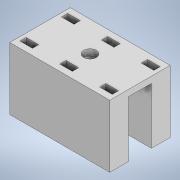
# Autodesk Inventor part: ghidaj_gaura
Saved by Autodesk Inventor 2022.6 (Build 266554000, 554)
## iProperties
Created: 2026-01-10
Part Number: ghidaj_gaura
Material: Generic
Document SubType Name: Modeling
Designer: Dragos Macovei
Density: 1 g/cm^3
Appearance: Default
Author: Dragos Macovei
Autodesk Inventor part; units mm, degrees
ref_plane "YZ Plane" through (0, 0, 0) normal (1, 0, 0) x (0, 1, 0)
ref_plane "XZ Plane" through (0, 0, 0) normal (0, 1, 0) x (-1, 0, 0)
ref_plane "XY Plane" through (0, 0, 0) normal (0, 0, 1) x (1, 0, 0)
sketch "Sketch1" plane through (0, 0, 0) normal (0, 1, 0) x (-1, 0, 0)
  line L0 (0, 0) -> (80, 0)
  line L1 (80, 0) -> (80, 18.3)
  line L2 (80, 18.3) -> (0, 18.3)
  line L3 (0, 18.3) -> (0, 0)
  dimension "d0" = 80
  dimension "d1" = 18.3
  constraints: 8 end point, 2 parallel, 1 horizontal, 1 perpendicular
  measures "d0" distance of L2.end L1.end
  measures "d1" distance of L0.end L1.end
extrude "Extrusion1" add sketch "Sketch1" along normal blind 5
sketch "Sketch2" plane through (0, 5, 0) normal (0, 1, 0) x (1, 0, 0)
  line L0 (-80, 0) -> (-80, -18.3) projected
  line L1 (-80, -18.3) -> (0, -18.3) projected
  line L2 (0, -18.3) -> (0, 0) projected
  line L3 (0, 0) -> (-80, 0) projected
  circle A0 centre (-40, -9.15) radius 5.05
  circle A1 centre (-40, -9.15) radius 9.15
  line L4 (0, 0) -> (-80, 0) projected
  dimension "d4" = 10.1
  constraints: 2 centre point, 1 coincident, 1 tangent
  measures "d4" diameter of A0
extrude "Extrusion2" cut sketch "Sketch2" against normal blind 5 contours A0
sketch "Sketch3" plane through (0, 5, 0) normal (0, 1, 0) x (1, 0, 0)
  circle A0 centre (-40, -9.15) radius 5.05 projected
  line L0 (-80, 0) -> (-80, -18.3) projected
  line L1 (-80, -18.3) -> (0, -18.3) projected
  line L2 (0, -18.3) -> (0, 0) projected
  line L3 (0, 0) -> (-80, 0) projected
  line L4 (-80, -18.3) -> (0, -18.3) projected
  line L5 (-80, -18.3) -> (0, -18.3)
  line L6 (0, -18.3) -> (0, -28.3)
  line L7 (0, -28.3) -> (-80, -28.3)
  line L8 (-80, -28.3) -> (-80, -18.3)
  line L9 (0, 0) -> (-80, 0) projected
  line L10 (-80, 0) -> (0, 0)
  line L11 (0, 0) -> (0, 10)
  line L12 (0, 10) -> (-80, 10)
  line L13 (-80, 10) -> (-80, 0)
  dimension "d7" = 10
  dimension "d8" = 10
  constraints: 16 end point, 4 parallel, 2 horizontal, 2 perpendicular, 1 point on line
  measures "d7" distance of L5.end L6.end
  measures "d8" distance of L11.end L10.end
extrude "Extrusion3" add sketch "Sketch3" against normal blind 50 contours L13 L12 L11 L3 | L1 L6 L7 L8
sketch "Sketch4" plane through (0, 5, 0) normal (0, 1, 0) x (1, 0, 0)
  circle A0 centre (-40, -9.15) radius 5.05 projected
  line L0 (-80, 10) -> (-80, -28.3) projected
  line L1 (-80, -28.3) -> (0, -28.3) projected
  line L2 (0, -28.3) -> (0, 10) projected
  line L3 (0, 10) -> (-80, 10) projected
  line L4 (0, -28.3) -> (-80, -28.3) projected
  line L5 (-80, 10) -> (0, 10) projected
  line L6 (-45.05, -28.3) -> (-34.95, -28.3)
  line L7 (-34.95, -28.3) -> (-34.95, -23.3)
  line L8 (-34.95, -23.3) -> (-45.05, -23.3)
  line L9 (-45.05, -23.3) -> (-45.05, -28.3)
  line L10 (-45.05, 10) -> (-34.95, 10)
  line L11 (-34.95, 10) -> (-34.95, 5)
  line L12 (-34.95, 5) -> (-45.05, 5)
  line L13 (-45.05, 5) -> (-45.05, 10)
  point P0 (0, 0)
  point P1 (-40, -28.3)
  point P2 (-40, 10)
  dimension "d11" = 5
  dimension "d12" = 5
  constraints: 16 end point, 5 point on line, 4 parallel, 2 horizontal, 2 midpoint, 2 perpendicular
  measures "d11" distance of L7.end L6.end
  measures "d12" distance of L10.end L11.end
extrude "Extrusion4" cut sketch "Sketch4" against normal through all contours L3 L11 L12 L13 | L9 L8 L7 L1
sketch "Sketch5" plane through (0, 5, 0) normal (0, 1, 0) x (1, 0, 0)
  line L0 (-34.95, 10) -> (-34.95, 5) projected
  line L1 (-34.95, 5) -> (-45.05, 5) projected
  line L2 (-45.05, 5) -> (-45.05, 10) projected
  line L3 (-45.05, 10) -> (-80, 10) projected
  line L4 (-80, 10) -> (-80, -28.3) projected
  line L5 (-80, -28.3) -> (-45.05, -28.3) projected
  line L6 (-45.05, -28.3) -> (-45.05, -23.3) projected
  line L7 (-45.05, -23.3) -> (-34.95, -23.3) projected
  line L8 (-34.95, -23.3) -> (-34.95, -28.3) projected
  line L9 (-34.95, -28.3) -> (0, -28.3) projected
  line L10 (0, -28.3) -> (0, 10) projected
  line L11 (0, 10) -> (-34.95, 10) projected
  circle A0 centre (-40, -9.15) radius 5.05 projected
  line L12 (-45.05, -28.3) -> (-80, -28.3) projected
  line L13 (-80, 10) -> (-45.05, 10) projected
  line L14 (-77, -28.3) -> (-66.9, -28.3)
  line L15 (-66.9, -28.3) -> (-66.9, -23.3)
  line L16 (-66.9, -23.3) -> (-77, -23.3)
  line L17 (-77, -23.3) -> (-77, -28.3)
  line L18 (-77, 10) -> (-66.9, 10)
  line L19 (-66.9, 10) -> (-66.9, 5)
  line L20 (-66.9, 5) -> (-77, 5)
  line L21 (-77, 5) -> (-77, 10)
  line L22 (0, 10) -> (0, 0) projected
  line L23 (-34.95, -28.3) -> (0, -28.3) projected
  line L24 (-13.1, -28.3) -> (-3, -28.3)
  line L25 (-3, -28.3) -> (-3, -23.3)
  line L26 (-3, -23.3) -> (-13.1, -23.3)
  line L27 (-13.1, -23.3) -> (-13.1, -28.3)
  line L28 (-13.1, 10) -> (-3, 10)
  line L29 (-3, 10) -> (-3, 5)
  line L30 (-3, 5) -> (-13.1, 5)
  line L31 (-13.1, 5) -> (-13.1, 10)
  point P0 (-66.9, 10)
  point P1 (-77, -25.8)
  point P2 (-77, 7.5)
  point P3 (-3, -25.8)
  point P4 (-8.05, -28.3)
  point P5 (-8.05, -23.3)
  point P6 (-8.05, 10)
  point P7 (-8.05, 5)
  point P8 (-3, 7.5)
  point P9 (-3, 10)
  point P10 (-3, -28.3)
  dimension "d15" = 10.1
  dimension "d16" = 10.1
  dimension "d21" = 3
  dimension "d22" = 10.1
  dimension "d23" = 3
  dimension "d24" = 3
  dimension "d25" = 10.1
  dimension "d26" = 5
  dimension "d27" = 5
  dimension "d28" = 5
  dimension "d29" = 10.1
  dimension "d30" = 3
  constraints: 32 end point, 8 midpoint, 8 parallel, 7 point on line, 4 horizontal, 4 perpendicular
  measures "d15" distance of point (-66.9, -28.3) L14.start
  measures "d16" distance of point (-66.9, 10) L18.start
  measures "d21" distance from line of point (-77, -25.8) L4
  measures "d22" distance between parallel lines of L15 L17
  measures "d23" distance from line of point (-77, 7.5) L4
  measures "d24" distance from line of L10 point (-3, -25.8)
  measures "d25" distance from line of L25 L26.end
  measures "d26" distance of point (-8.05, -28.3) point (-8.05, -23.3)
  measures "d27" distance from line of L8.end L7
  measures "d28" distance of point (-8.05, 10) point (-8.05, 5)
  measures "d29" distance from line of point (-3, 7.5) L31
  measures "d30" distance from line of L10 L29.end
extrude "Extrusion5" cut sketch "Sketch5" against normal through all contours L11 L29 L30 L31 | L19 L20 L21 L3 | L9 L27 L26 L25 | L17 L16 L15 L5
sketch "Sketch6" plane through (0, 5, 0) normal (0, 1, 0) x (1, 0, 0)
  circle A0 centre (-40, -9.15) radius 5.05 projected
  line L0 (-77, -28.3) -> (-77, -23.3) projected
  line L1 (-77, -23.3) -> (-66.9, -23.3) projected
  line L2 (-66.9, -23.3) -> (-66.9, -28.3) projected
  line L3 (-66.9, -28.3) -> (-45.05, -28.3) projected
  line L4 (-45.05, -28.3) -> (-45.05, -23.3) projected
  line L5 (-45.05, -23.3) -> (-34.95, -23.3) projected
  line L6 (-34.95, -23.3) -> (-34.95, -28.3) projected
  line L7 (-34.95, -28.3) -> (-13.1, -28.3) projected
  line L8 (-13.1, -28.3) -> (-13.1, -23.3) projected
  line L9 (-13.1, -23.3) -> (-3, -23.3) projected
  line L10 (-3, -23.3) -> (-3, -28.3) projected
  line L11 (-3, -28.3) -> (0, -28.3) projected
  line L12 (0, -28.3) -> (0, 10) projected
  line L13 (0, 10) -> (-3, 10) projected
  line L14 (-3, 10) -> (-3, 5) projected
  line L15 (-3, 5) -> (-13.1, 5) projected
  line L16 (-13.1, 5) -> (-13.1, 10) projected
  line L17 (-13.1, 10) -> (-34.95, 10) projected
  line L18 (-34.95, 10) -> (-34.95, 5) projected
  line L19 (-34.95, 5) -> (-45.05, 5) projected
  line L20 (-45.05, 5) -> (-45.05, 10) projected
  line L21 (-45.05, 10) -> (-66.9, 10) projected
  line L22 (-66.9, 10) -> (-66.9, 5) projected
  line L23 (-66.9, 5) -> (-77, 5) projected
  line L24 (-77, 5) -> (-77, 10) projected
  line L25 (-77, 10) -> (-80, 10) projected
  line L26 (-80, 10) -> (-80, -28.3) projected
  line L27 (-80, -28.3) -> (-77, -28.3) projected
  line L28 (-80, -33.3) -> (0, -33.3)
  line L29 (0, -33.3) -> (0, 15)
  line L30 (0, 15) -> (-80, 15)
  line L31 (-80, 15) -> (-80, -33.3)
  line L32 (-80, 10) -> (0, 10)
  line L33 (-80, -28.3) -> (-77, -28.3) projected
  line L34 (-80, -28.3) -> (0, -28.3)
  point P0 (0, 0)
  point P1 (-78.5, 10)
  point P2 (-78.5, -28.3)
  point P3 (-13.1, -28.3)
  dimension "d31" = 5
  dimension "d32" = 5
  constraints: 12 end point, 3 horizontal, 3 point on line, 2 midpoint, 2 parallel, 1 perpendicular
  measures "d31" distance from line of L30 point (-78.5, 10)
  measures "d32" distance from line of point (-78.5, -28.3) L28
extrude "Extrusion6" add sketch "Sketch6" against normal up to surface (50 mm away) contours L34 L3 L7 L11 L29 L28 L31 L27 | L31 L30 L29 L13 L32 L17 L21 L25
equation "\"d16\" = d15"
equation "\"d22\" = d15"
equation "\"d25\" = d15"
equation "\"d26\" = d27"
equation "\"d28\" = d27"
equation "\"d29\" = d25"
equation "\"d30\" = d24"
equation "\"d31\" = d32"
body "Solid1"
